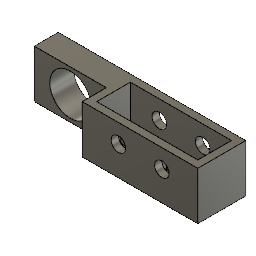
Soutiens fin de course gauche v1 (Autodesk Fusion 360 design; units mm, degrees)
Autodesk Fusion 360 part; units mm, degrees
sketch "Sketch1" plane through (0, 0, 0) normal (0, 1, 0) x (1, 0, 0)
  line L0 (0, 0) -> (24, 0)
  line L1 (24, 0) -> (24, 10)
  line L2 (24, 10) -> (0, 10)
  line L3 (0, 10) -> (0, 0)
  line L4 (1.5, 8.5) -> (22.5, 8.5)
  line L5 (22.5, 8.5) -> (22.5, 1.5)
  line L6 (22.5, 1.5) -> (1.5, 1.5)
  line L7 (1.5, 1.5) -> (1.5, 8.5)
  line L8 (1.5, 6.5) -> (6, 6.5)
  line L9 (6, 6.5) -> (6, 3.5)
  line L10 (6, 3.5) -> (1.5, 3.5)
  line L11 (1.5, 3.5) -> (1.5, 6.5)
  line L12 (15.5, 6.5) -> (11, 6.5)
  line L13 (11, 6.5) -> (11, 3.5)
  line L14 (11, 3.5) -> (15.5, 3.5)
  line L15 (15.5, 3.5) -> (15.5, 6.5)
  line L16 (22.5, 6.5) -> (18, 6.5)
  line L17 (18, 6.5) -> (18, 3.5)
  line L18 (18, 3.5) -> (22.5, 3.5)
  line L19 (22.5, 3.5) -> (22.5, 6.5)
  line L20 (-15, 5) -> (0, 5)
  line L21 (0, 5) -> (0, 0)
  line L22 (-15, 5) -> (-15, 10)
  line L23 (-15, 10) -> (0, 10)
  dimension "d1" = 24
  dimension "d2" = 10
  dimension "d6" = 21
  dimension "d7" = 7
  dimension "d10" = 4.5
  dimension "d11" = 3
  dimension "d24" = 5
  measures "d1" distance of L0.start
  measures "d2" distance of L0.start
  measures "d24" distance of L0.start
extrude "Extrude1" add sketch "Sketch1" along normal blind 3 contours L4 L5 L6 L7 L8 L9 L10 L16 L17 L18
extrude "Extrude2" add sketch "Sketch1" along normal blind 10 contours L0 L1 L2 L3 L21 | L3 L20 L22 L23
sketch "Sketch2" plane through (0, 0, 0) normal (0, 0, 1) x (1, 0, 0)
  line L0 (0, 0) -> (24, 0)
  line L1 (24, 0) -> (24, 10)
  line L2 (24, 10) -> (0, 10)
  circle A0 centre (7.5, 6.1) radius 1.5
  circle A1 centre (16.526, 6.0981) radius 1.5
  circle A2 centre (-7.5, 5) radius 4.25
  line L3 (0, 10) -> (0, 0)
  dimension "d19" = 3
  dimension "d20" = 3
  dimension "d26" = 8.5
  measures "d19" diameter of A0
  measures "d20" diameter of A1
  measures "d26" diameter of A2
extrude "Extrude3" cut sketch "Sketch2" against normal blind 10 contours A0 | A1 | A2
